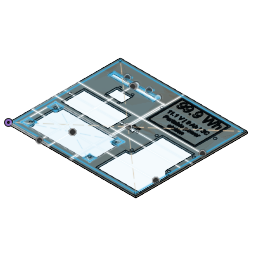
Front panel (Autodesk Fusion 360 design; units mm, degrees)
Autodesk Fusion 360 part; units mm, degrees
sketch "Sketch1" plane through (0, 0, 0) normal (0, 0, 1) x (1, 0, 0)
  line L0 (0, 0) -> (200, 0)
  line L1 (200, 0) -> (200, 150)
  line L2 (200, 150) -> (0, 150)
  line L3 (0, 150) -> (0, 0)
  dimension "d1" = 200
  dimension "d2" = 150
  constraint horizontal L0
  constraint vertical L1
  constraint horizontal L2
  constraint vertical L3
  constraint coincident L0.start L3.end
  measures "d1" distance of L0.start L0.end
  measures "d2" distance of L0.start L2.end
extrude "Extrude1" add sketch "Sketch1" along normal blind 3
sketch "Sketch2" plane through (0, 0, 3) normal (0, 0, 1) x (-1, 0, 0)
  line L0 (0, -150) -> (0, 0)
  line L1 (0, 0) -> (-200, 0)
  line L2 (-200, 0) -> (-200, -150)
  line L3 (-200, -150) -> (0, -150)
  line L4 (-100, -150) -> (-100, 0)
  line L5 (0, -75) -> (-200, -75)
  line L6 (-100, -150) -> (-50, -150)
  line L7 (-50, -150) -> (-50, 0)
  line L8 (0, -75) -> (0, -112.5)
  line L9 (0, -112.5) -> (-200, -112.5)
  line L10 (0, -75) -> (0, -37.5)
  line L11 (0, -37.5) -> (-200, -37.5)
  dimension "d5" = 50
  dimension "d6" = 37.5
  dimension "d7" = 37.5
  constraint midpoint L3 L4.start
  constraint midpoint L1 L4.end
  constraint midpoint L0 L5.start
  constraint midpoint L2 L5.end
  constraint coincident L3 L6.end
  constraint coincident L1 L7.end
  constraint perpendicular L1 L7
  constraint perpendicular L3 L8
  constraint coincident L2 L9.end
  constraint perpendicular L2 L9
  constraint perpendicular L5 L10
  constraint coincident L2 L11.end
  constraint perpendicular L2 L11
  measures "d5" distance of L4.start L6.end
  measures "d6" distance of L5.start L8.end
  measures "d7" distance of L5.start L10.end
sketch "Sketch3" plane through (0, 0, 3) normal (0, 0, 1) x (-1, 0, 0)
  line L0 (-103.25, -144.25) -> (-188.75, -144.25)
  circle A0 centre (-103.25, -144.25) radius 2.1
  circle A1 centre (-188.75, -144.25) radius 2.1
  line L1 (-103.25, -144.25) -> (-146, -144.25)
  line L2 (-194, -126.75) -> (-194, -161.75)
  line L3 (-194, -161.75) -> (-98, -161.75)
  line L4 (-98, -161.75) -> (-98, -126.75)
  line L5 (-98, -126.75) -> (-194, -126.75)
  line L6 (-194, -126.75) -> (-98, -161.75) construction
  line L7 (-194, -161.75) -> (-98, -126.75) construction
  point P0 (-146, -144.25)
  dimension "d8" = 85.5
  dimension "d9" = 4.2
  dimension "d10" = 4.2
  dimension "d11" = 42.75
  dimension "d12" = 35
  dimension "d13" = 96
  constraint coincident L0.start A0.centre
  constraint coincident L0.end A1.centre
  constraint midpoint L0 P0
  constraint perpendicular L2 L3
  constraint parallel L2 L4
  constraint parallel L3 L5
  constraint coincident L6 P0
  constraint coincident L7 P0
  constraint coincident P0 L1.end
  measures "d8" distance of L0.start L0.end
  measures "d9" diameter of A0
  measures "d10" diameter of A1
  measures "d11" distance of L0.start P0
  measures "d12" distance of L3.end L4.end
  measures "d13" distance of L2.end L3.end
sketch "Sketch4" plane through (0, 0, 3) normal (0, 0, 1) x (-1, 0, 0)
  line L0 (-167.8105, -105.7768) -> (-167.8105, -106)
  line L1 (-167.8105, -106) -> (-167.8105, -7.9943)
  line L2 (-202.8105, -7.9972) -> (-132.8105, -7.9972)
  line L3 (-132.8105, -7.9972) -> (-132.8105, -105.9972)
  line L4 (-132.8105, -105.9972) -> (-202.8105, -105.9972)
  line L5 (-202.8105, -105.9972) -> (-202.8105, -7.9972)
  line L6 (-202.8105, -7.9972) -> (-132.8105, -105.9972) construction
  line L7 (-132.8105, -7.9972) -> (-202.8105, -105.9972) construction
  line L8 (-64, -118.5) -> (-38, -118.5)
  line L9 (-38, -118.5) -> (-38, -136.5)
  line L10 (-38, -136.5) -> (-64, -136.5)
  line L11 (-64, -136.5) -> (-64, -118.5)
  line L12 (-64, -118.5) -> (-38, -136.5) construction
  line L13 (-38, -118.5) -> (-64, -136.5) construction
  line L14 (-61.25, -116) -> (-40.75, -116)
  line L15 (-40.75, -116) -> (-40.75, -139)
  line L16 (-40.75, -139) -> (-61.25, -139)
  line L17 (-61.25, -139) -> (-61.25, -116)
  line L18 (-61.25, -116) -> (-40.75, -139) construction
  line L19 (-40.75, -116) -> (-61.25, -139) construction
  circle A0 centre (-40.75, -139) radius 1.7
  circle A1 centre (-61.25, -139) radius 1.7
  circle A2 centre (-40.75, -116) radius 1.7
  circle A3 centre (-61.25, -116) radius 1.7
  point P0 (-167.8105, -56.9972)
  point P1 (-51, -127.5)
  point P2 (-51, -127.5)
  dimension "d15" = 70
  dimension "d16" = 98
  dimension "d17" = 26
  dimension "d18" = 18
  dimension "d19" = 20.5
  dimension "d20" = 23
  dimension "d21" = 3.4
  dimension "d22" = 3.4
  dimension "d23" = 3.4
  dimension "d24" = 3.4
  constraint horizontal L2
  constraint perpendicular L2 L3
  constraint parallel L2 L4
  constraint parallel L3 L5
  constraint coincident L6 P0
  constraint coincident L7 P0
  constraint midpoint L1 P0
  constraint horizontal L8
  constraint perpendicular L8 L9
  constraint parallel L8 L10
  constraint parallel L9 L11
  constraint coincident L12 P2
  constraint coincident L13 P2
  constraint horizontal L14
  constraint perpendicular L14 L15
  constraint parallel L14 L16
  constraint parallel L15 L17
  constraint coincident L18 P2
  constraint coincident L19 P2
  constraint coincident P2 P1
  constraint coincident L15.end L16.start
  constraint coincident L16.end L17.start
  constraint coincident L14.end L15.start
  constraint coincident L14.start L17.end
  measures "d15" distance of L3.end L4.end
  measures "d16" distance of L2.end L3.end
  measures "d17" distance of L9.end L10.end
  measures "d18" distance of L8.end L9.end
  measures "d19" distance of L15.end L16.end
  measures "d20" distance of L14.end L15.end
  measures "d21" diameter of A0
  measures "d22" diameter of A1
  measures "d23" diameter of A2
  measures "d24" diameter of A3
sketch "Sketch5" plane through (0, 0, 3) normal (0, 0, 1) x (-1, 0, 0)
  line L0 (-51, -144) -> (-51, -158)
  line L1 (-51, -158) -> (-68.5, -158)
  line L2 (-68.5, -158) -> (-33.5, -158)
  circle A0 centre (-68.5, -158) radius 1.7
  circle A1 centre (-33.5, -158) radius 1.7
  dimension "d25" = 14
  dimension "d26" = 17.5
  dimension "d27" = 35
  dimension "d28" = 3.4
  dimension "d29" = 3.4
  constraint vertical L0
  constraint perpendicular L0 L1
  constraint parallel L1 L2
  constraint coincident L1.end L2.start
  constraint coincident L2.end A1.centre
  measures "d25" distance of L0.start L0.end
  measures "d26" distance of L0.end L1.end
  measures "d27" distance of L1.end L2.end
  measures "d28" diameter of A0
  measures "d29" diameter of A1
sketch "Sketch6" plane through (0, 0, 3) normal (0, 0, 1) x (-1, 0, 0)
  line L0 (-37, -154.5) -> (-30, -154.5)
  line L1 (-30, -154.5) -> (-30, -161.5)
  line L2 (-30, -161.5) -> (-37, -161.5)
  line L3 (-37, -161.5) -> (-37, -154.5)
  line L4 (-37, -154.5) -> (-30, -161.5) construction
  line L5 (-30, -154.5) -> (-37, -161.5) construction
  line L6 (-72, -154.5) -> (-65, -154.5)
  line L7 (-65, -154.5) -> (-65, -161.5)
  line L8 (-65, -161.5) -> (-72, -161.5)
  line L9 (-72, -161.5) -> (-72, -154.5)
  line L10 (-72, -154.5) -> (-65, -161.5) construction
  line L11 (-65, -154.5) -> (-72, -161.5) construction
  line L12 (-30, -154.5) -> (-16, -154.5)
  line L13 (-72, -154.5) -> (-86, -154.5)
  line L14 (-16, -154.5) -> (-86, -154.5)
  line L15 (-86, -154.5) -> (-86, -147.5)
  line L16 (-86, -147.5) -> (-16, -147.5)
  line L17 (-16, -147.5) -> (-16, -154.5)
  point P0 (-33.5, -158)
  point P1 (-68.5, -158)
  dimension "d30" = 7
  dimension "d31" = 7
  dimension "d32" = 7
  dimension "d33" = 7
  dimension "d34" = 14
  dimension "d35" = 14
  dimension "d36" = 7
  constraint horizontal L0
  constraint perpendicular L0 L1
  constraint parallel L0 L2
  constraint parallel L1 L3
  constraint coincident L4 P0
  constraint coincident L5 P0
  constraint horizontal L6
  constraint perpendicular L6 L7
  constraint parallel L6 L8
  constraint parallel L7 L9
  constraint coincident L10 P1
  constraint coincident L11 P1
  constraint perpendicular L1 L12
  constraint perpendicular L9 L13
  constraint horizontal L14
  constraint vertical L15
  constraint horizontal L16
  constraint vertical L17
  measures "d30" distance of L1.end L2.end
  measures "d31" distance of L0.end L1.end
  measures "d32" distance of L7.end L8.end
  measures "d33" distance of L6.end L7.end
  measures "d34" distance of L0.end L12.end
  measures "d35" distance of L6.start L13.end
  measures "d36" distance of L12.end L16.end
sketch "Sketch7" plane through (0, 0, 3) normal (0, 0, 1) x (-1, 0, 0)
  line L0 (-51, -154.5) -> (-51, -151)
  line L1 (-87, -146.5) -> (-15, -146.5)
  line L2 (-15, -146.5) -> (-15, -155.5)
  line L3 (-15, -155.5) -> (-87, -155.5)
  line L4 (-87, -155.5) -> (-87, -146.5)
  line L5 (-87, -146.5) -> (-15, -155.5) construction
  line L6 (-15, -146.5) -> (-87, -155.5) construction
  point P0 (-51, -151)
  dimension "d37" = 3.5
  dimension "d38" = 72
  dimension "d39" = 9
  constraint vertical L0
  constraint horizontal L1
  constraint perpendicular L1 L2
  constraint parallel L1 L3
  constraint parallel L2 L4
  constraint coincident L5 P0
  constraint coincident L6 P0
  constraint coincident P0 L0.end
  measures "d37" distance of L0.start P0
  measures "d38" distance of L2.end L3.end
  measures "d39" distance of L1.end L2.end
sketch "Sketch8" plane through (0, 0, 3) normal (0, 0, 1) x (-1, 0, 0)
  line L0 (-51, -165) -> (-51, -15)
  line L1 (-13.5, -108.5) -> (-88.5, -108.5)
  line L2 (-88.5, -108.5) -> (-88.5, -71.5)
  line L3 (-88.5, -71.5) -> (-13.5, -71.5)
  line L4 (-13.5, -71.5) -> (-13.5, -108.5)
  line L5 (-13.5, -108.5) -> (-88.5, -71.5) construction
  line L6 (-88.5, -108.5) -> (-13.5, -71.5) construction
  point P0 (-51, -90)
  dimension "d40" = 75
  dimension "d41" = 37
  constraint vertical L0
  constraint horizontal L1
  constraint perpendicular L1 L2
  constraint parallel L1 L3
  constraint parallel L2 L4
  constraint coincident L5 P0
  constraint coincident L6 P0
  constraint midpoint L0 P0
  measures "d40" distance of L2.end L3.end
  measures "d41" distance of L1.end L2.end
extrude "Extrude2" add 1 faces at (200, 50, 1) along direction (1, 0, 0) blind 5
sketch "Sketch9" plane through (0, 0, 3) normal (0, 0, 1) x (-1, 0, 0)
  line L0 (0, 0) -> (-4, 0)
  line L1 (-4, 0) -> (-4, -4)
  line L2 (-4, -4) -> (0, -4)
  line L3 (0, -4) -> (0, 0)
  dimension "d44" = 4
  dimension "d45" = 4
  constraint horizontal L0
  constraint vertical L1
  constraint horizontal L2
  constraint vertical L3
  constraint coincident L0.start L3.end
  measures "d44" distance of L0.start L0.end
  measures "d45" distance of L0.start L2.end
extrude "Extrude3" add 1 faces at (136.6667, 150, 1) along direction (0, 1, 0) blind 30
sketch "Sketch10" plane through (0, 0, 3) normal (0, 0, 1) x (-1, 0, 0)
  line L0 (0, 0) -> (-65, 0)
  line L1 (-65, 0) -> (-65, -38.25)
  line L2 (-120, -10.75) -> (-10, -10.75)
  line L3 (-10, -10.75) -> (-10, -65.75)
  line L4 (-10, -65.75) -> (-120, -65.75)
  line L5 (-120, -65.75) -> (-120, -10.75)
  line L6 (-120, -10.75) -> (-10, -65.75) construction
  line L7 (-10, -10.75) -> (-120, -65.75) construction
  point P0 (-65, -38.25)
  dimension "d50" = 65
  dimension "d51" = 38.25
  dimension "d52" = 110
  dimension "d53" = 55
  constraint coincident L0.start origin
  constraint horizontal L0
  constraint perpendicular L0 L1
  constraint horizontal L2
  constraint perpendicular L2 L3
  constraint parallel L2 L4
  constraint parallel L3 L5
  constraint coincident L6 P0
  constraint coincident L7 P0
  constraint coincident P0 L1.end
  measures "d50" distance of L0.start L0.end
  measures "d51" distance of L0.end P0
  measures "d52" distance of L3.end L4.end
  measures "d53" distance of L2.end L3.end
sketch "Sketch11" plane through (0, 0, 3) normal (0, 0, 1) x (-1, 0, 0)
  line L0 (0, -180) -> (0, 0)
  line L1 (0, 0) -> (-205, 0)
  line L2 (-205, 0) -> (-205, -180)
  line L3 (-205, -180) -> (0, -180)
  line L4 (-88, -146.5) -> (-14, -146.5)
  line L5 (-14, -146.5) -> (-14, -155.5)
  line L6 (-14, -155.5) -> (-88, -155.5)
  line L7 (-88, -155.5) -> (-88, -146.5)
  line L8 (-88, -146.5) -> (-14, -155.5) construction
  line L9 (-14, -146.5) -> (-88, -155.5) construction
  point P0 (-51, -151)
  dimension "d54" = 74
  dimension "d55" = 9
  constraint horizontal L4
  constraint perpendicular L4 L5
  constraint parallel L4 L6
  constraint parallel L5 L7
  constraint coincident L8 P0
  constraint coincident L9 P0
  measures "d54" distance of L5.end L6.end
  measures "d55" distance of L4.end L5.end
sketch "Sketch12" plane through (0, 0, 3) normal (0, 0, 1) x (-1, 0, 0)
  line L0 (-132.75, -106) -> (-141.75, -106)
  line L1 (-141.75, -106) -> (-141.75, -56)
  line L2 (-141.75, -56) -> (-132.75, -56)
  line L3 (-132.75, -56) -> (-132.75, -106)
  line L4 (-202.75, -106) -> (-193.75, -106)
  line L5 (-193.75, -106) -> (-193.75, -56)
  line L6 (-193.75, -56) -> (-202.75, -56)
  line L7 (-202.75, -56) -> (-202.75, -106)
  line L8 (-132.75, -106) -> (-167.75, -106)
  line L9 (-167.75, -106) -> (-167.75, -81)
  line L10 (-197.75, -61) -> (-137.75, -61)
  line L11 (-137.75, -61) -> (-137.75, -101)
  line L12 (-137.75, -101) -> (-197.75, -101)
  line L13 (-197.75, -101) -> (-197.75, -61)
  line L14 (-197.75, -61) -> (-137.75, -101) construction
  line L15 (-137.75, -61) -> (-197.75, -101) construction
  circle A0 centre (-137.75, -61) radius 2.1
  circle A1 centre (-137.75, -101) radius 2.1
  circle A2 centre (-197.75, -101) radius 2.1
  circle A3 centre (-197.75, -61) radius 2.1
  point P0 (-167.75, -81)
  dimension "d56" = 9
  dimension "d57" = 50
  dimension "d58" = 9
  dimension "d59" = 50
  dimension "d60" = 35
  dimension "d61" = 25
  dimension "d62" = 60
  dimension "d63" = 40
  dimension "d64" = 4.2
  dimension "d65" = 4.2
  dimension "d66" = 4.2
  dimension "d67" = 4.2
  constraint horizontal L0
  constraint vertical L1
  constraint horizontal L2
  constraint vertical L3
  constraint horizontal L4
  constraint vertical L5
  constraint horizontal L6
  constraint vertical L7
  constraint perpendicular L7 L8
  constraint perpendicular L8 L9
  constraint horizontal L10
  constraint perpendicular L10 L11
  constraint parallel L10 L12
  constraint parallel L11 L13
  constraint coincident L14 P0
  constraint coincident L15 P0
  constraint coincident P0 L9.end
  constraint coincident L10.end L11.start
  constraint coincident L11.end L12.start
  constraint coincident L12.end L13.start
  constraint coincident L10.start L13.end
  measures "d56" distance of L0.start L0.end
  measures "d57" distance of L0.start L2.end
  measures "d58" distance of L4.start L4.end
  measures "d59" distance of L4.start L6.end
  measures "d60" distance of L0.start L8.end
  measures "d61" distance of L8.end P0
  measures "d62" distance of L11.end L12.end
  measures "d63" distance of L10.end L11.end
  measures "d64" diameter of A0
  measures "d65" diameter of A1
  measures "d66" diameter of A2
  measures "d67" diameter of A3
sketch "Sketch13" plane through (0, 0, 3) normal (0, 0, 1) x (-1, 0, 0)
  line L0 (-112.5, -18.25) -> (-17.5, -18.25)
  line L1 (-17.5, -18.25) -> (-17.5, -58.25)
  line L2 (-17.5, -58.25) -> (-112.5, -58.25)
  line L3 (-112.5, -58.25) -> (-112.5, -18.25)
  line L4 (-112.5, -18.25) -> (-17.5, -58.25) construction
  line L5 (-17.5, -18.25) -> (-112.5, -58.25) construction
  circle A0 centre (-17.5, -58.25) radius 2.1
  circle A1 centre (-112.5, -58.25) radius 2.1
  circle A2 centre (-112.5, -18.25) radius 2.1
  circle A3 centre (-17.5, -18.25) radius 2.1
  line L6 (-9, -90) -> (-93, -90)
  circle A4 centre (-9, -90) radius 2.1
  circle A5 centre (-93, -90) radius 2.1
  point P0 (-65, -38.25)
  point P1 (-51, -90)
  dimension "d68" = 95
  dimension "d69" = 40
  dimension "d70" = 4.2
  dimension "d71" = 4.2
  dimension "d72" = 4.2
  dimension "d73" = 4.2
  dimension "d74" = 84
  dimension "d75" = 4.2
  dimension "d76" = 4.2
  constraint horizontal L0
  constraint perpendicular L0 L1
  constraint parallel L0 L2
  constraint parallel L1 L3
  constraint coincident L4 P0
  constraint coincident L5 P0
  constraint coincident L1.end L2.start
  constraint coincident L2.end L3.start
  constraint coincident L0.start L3.end
  constraint coincident L0.end L1.start
  constraint midpoint L6 P1
  constraint horizontal L6
  constraint coincident L6.start A4.centre
  constraint coincident L6.end A5.centre
  measures "d68" distance of L1.end L2.end
  measures "d69" distance of L0.end L1.end
  measures "d70" diameter of A0
  measures "d71" diameter of A1
  measures "d72" diameter of A2
  measures "d73" diameter of A3
  measures "d74" distance of L6.start L6.end
  measures "d75" diameter of A4
  measures "d76" diameter of A5
sketch "Sketch14" plane through (0, 0, 3) normal (0, 0, 1) x (-1, 0, 0)
  line L0 (-10, -10.75) -> (-22, -10.75)
  line L1 (-22, -10.75) -> (-22, -22.75)
  line L2 (-22, -22.75) -> (-10, -22.75)
  line L3 (-10, -22.75) -> (-10, -10.75)
  line L4 (-10, -65.75) -> (-22, -65.75)
  line L5 (-22, -65.75) -> (-22, -53.75)
  line L6 (-22, -53.75) -> (-10, -53.75)
  line L7 (-10, -53.75) -> (-10, -65.75)
  line L8 (-120, -65.75) -> (-110, -65.75)
  line L9 (-110, -65.75) -> (-110, -55.75)
  line L10 (-110, -55.75) -> (-120, -55.75)
  line L11 (-120, -55.75) -> (-120, -65.75)
  line L12 (-120, -10.75) -> (-110, -10.75)
  line L13 (-110, -10.75) -> (-110, -20.75)
  line L14 (-110, -20.75) -> (-120, -20.75)
  line L15 (-120, -20.75) -> (-120, -10.75)
  dimension "d77" = 12
  dimension "d78" = 12
  dimension "d79" = 12
  dimension "d80" = 12
  dimension "d81" = 10
  dimension "d82" = 10
  dimension "d83" = 10
  constraint horizontal L0
  constraint vertical L1
  constraint horizontal L2
  constraint vertical L3
  constraint horizontal L4
  constraint vertical L5
  constraint horizontal L6
  constraint vertical L7
  constraint horizontal L8
  constraint vertical L9
  constraint horizontal L10
  constraint vertical L11
  constraint horizontal L12
  constraint vertical L13
  constraint horizontal L14
  constraint vertical L15
  measures "d77" distance of L0.start L0.end
  measures "d78" distance of L0.start L2.end
  measures "d79" distance of L4.start L4.end
  measures "d80" distance of L4.start L6.end
  measures "d81" distance of L8.start L10.end
  measures "d82" distance of L12.start L12.end
  measures "d83" distance of L12.start L14.end
sketch "Sketch15" plane through (0, 0, 3) normal (0, 0, 1) x (-1, 0, 0)
  line L0 (0, -180) -> (-102.5, -180)
  line L1 (-102.5, -180) -> (-102.5, 0)
  line L2 (-113.5, -86.5) -> (-106.5, -86.5)
  line L3 (-106.5, -86.5) -> (-106.5, -93.5)
  line L4 (-106.5, -93.5) -> (-113.5, -93.5)
  line L5 (-113.5, -93.5) -> (-113.5, -86.5)
  line L6 (-113.5, -86.5) -> (-106.5, -93.5) construction
  line L7 (-106.5, -86.5) -> (-113.5, -93.5) construction
  line L8 (-102.5, -90) -> (-117.5, -90)
  circle A0 centre (-102.5, -90) radius 1.7
  circle A1 centre (-117.5, -90) radius 1.7
  point P0 (-110, -90)
  point P1 (-110, -90)
  dimension "d84" = 102.5
  dimension "d85" = 7
  dimension "d86" = 7
  dimension "d87" = 15
  dimension "d88" = 3.4
  dimension "d89" = 3.4
  constraint horizontal L0
  constraint perpendicular L0 L1
  constraint horizontal L2
  constraint perpendicular L2 L3
  constraint parallel L2 L4
  constraint parallel L3 L5
  constraint coincident L6 P1
  constraint coincident L7 P1
  constraint midpoint L8 P1
  constraint coincident P1 P0
  constraint perpendicular L5 L8
  constraint coincident L8.start A0.centre
  constraint coincident L8.end A1.centre
  measures "d84" distance of L0.start L0.end
  measures "d85" distance of L3.end L4.end
  measures "d86" distance of L2.end L3.end
  measures "d87" distance of L8.start L8.end
  measures "d88" diameter of A0
  measures "d89" diameter of A1
sketch "Sketch16" plane through (0, 0, 3) normal (0, 0, 1) x (-1, 0, 0)
  line L0 (-17.5, -53.75) -> (-17.5, -22.75)
  line L1 (-17.5, -22.75) -> (-22, -22.75)
  line L2 (-22, -22.75) -> (-22, -10.75)
  line L3 (-22, -10.75) -> (-110, -10.75)
  line L4 (-110, -10.75) -> (-110, -20.75)
  line L5 (-110, -20.75) -> (-120, -20.75)
  line L6 (-120, -20.75) -> (-120, -55.75)
  line L7 (-120, -55.75) -> (-110, -55.75)
  line L8 (-110, -55.75) -> (-110, -65.75)
  line L9 (-110, -65.75) -> (-22, -65.75)
  line L10 (-22, -65.75) -> (-22, -53.75)
  line L11 (-22, -53.75) -> (-17.5, -53.75)
  line L12 (-141.75, -106) -> (-141.75, -56)
  line L13 (-141.75, -56) -> (-132.75, -56)
  line L14 (-132.75, -56) -> (-132.75, -8)
  line L15 (-132.75, -8) -> (-202.8, -8)
  line L16 (-132.75, -8) -> (-202.8, -8)
  line L17 (-202.8, -8) -> (-202.8, -56)
  line L18 (-202.8, -56) -> (-193.8, -56)
  line L19 (-193.8, -56) -> (-193.8, -106)
  line L20 (-193.8, -106) -> (-141.75, -106)
  dimension "d90" = 90
  dimension "d91" = 48
  dimension "d92" = 70.05
  constraint vertical L0
  constraint perpendicular L0 L1
  constraint perpendicular L1 L2
  constraint perpendicular L0 L3
  constraint perpendicular L3 L4
  constraint perpendicular L4 L5
  constraint perpendicular L5 L6
  constraint perpendicular L6 L7
  constraint perpendicular L7 L8
  constraint perpendicular L8 L9
  constraint perpendicular L9 L10
  constraint perpendicular L0 L11
  constraint perpendicular L9 L12
  constraint perpendicular L8 L13
  constraint perpendicular L14 L15
  constraint perpendicular L15 L17
  constraint perpendicular L17 L18
  constraint perpendicular L15 L19
  measures "d90" angle of L13 L14
  measures "d91" distance of L13.end L14.end
  measures "d92" distance of L14.end L15.end
extrude "Extrude4" cut sketch "Sketch16" sketch "Sketch13" sketch "Sketch8" sketch "Sketch4" sketch "Sketch11" sketch "Sketch5" sketch "Sketch3" sketch "Sketch15" sketch "Sketch12" against normal blind 8767865 of sketch 2 contours L0 L3 A2 | L0 L3 A2 | L0 L1 A3 | L0 L1 A3 | L2 L3 A1 | L2 L3 A1 | L1 L2 A0 | L1 L2 A0 | A4 | A5 of sketch 3 of sketch 4 contours L8 L10 L11 L17 | L8 L10 L15 L17 | L8 L9 L10 L15 | L14 L17 A3 | L14 L17 A3 | L14 L15 A2 | L14 L15 A2 | L16 L17 A1 | L16 L17 A1 | L15 L16 A0 | L15 L16 A0 of sketch 5 contours L4 L5 L6 L7 of sketch 6 of sketch 7 contours A0 | A1 of sketch 8 of sketch 9 contours L11 L12 A1 | L11 L12 A1 | L10 L11 A0 | L10 L11 A0 | L10 L13 A3 | L10 L13 A3 | L12 L13 A2 | L12 L13 A2
sketch "Sketch17" plane through (0, 0, 3) normal (0, 0, 1) x (-1, 0, 0)
  line L0 (0, -180) -> (0, 0)
  line L1 (0, 0) -> (-205, 0)
  line L2 (-205, 0) -> (-205, -180)
  line L3 (-205, -180) -> (0, -180)
  circle A0 centre (-197.75, -101) radius 2.1
  circle A1 centre (-137.75, -101) radius 2.1
  circle A2 centre (-117.5, -90) radius 1.7
  circle A3 centre (-102.5, -90) radius 1.7
  circle A4 centre (-103.25, -144.25) radius 2.1
  circle A5 centre (-33.5, -158) radius 1.7
  circle A6 centre (-40.75, -116) radius 1.7
  line L4 (-38, -118.5) -> (-38, -136.5)
  line L5 (-38, -136.5) -> (-64, -136.5)
  line L6 (-64, -136.5) -> (-64, -118.5)
  line L7 (-64, -118.5) -> (-38, -118.5)
  circle A7 centre (-61.25, -116) radius 1.7
  circle A8 centre (-112.5, -18.25) radius 2.1
  circle A9 centre (-93, -90) radius 2.1
  circle A10 centre (-9, -90) radius 2.1
  line L8 (-17.5, -22.75) -> (-17.5, -53.75)
  line L9 (-17.5, -53.75) -> (-22, -53.75)
  line L10 (-22, -53.75) -> (-22, -65.75)
  line L11 (-22, -65.75) -> (-110, -65.75)
  line L12 (-110, -65.75) -> (-110, -55.75)
  line L13 (-110, -55.75) -> (-120, -55.75)
  line L14 (-120, -55.75) -> (-120, -20.75)
  line L15 (-120, -20.75) -> (-110, -20.75)
  line L16 (-110, -20.75) -> (-110, -10.75)
  line L17 (-110, -10.75) -> (-22, -10.75)
  line L18 (-22, -10.75) -> (-22, -22.75)
  line L19 (-22, -22.75) -> (-17.5, -22.75)
  line L20 (-141.75, -56) -> (-141.75, -106)
  line L21 (-141.75, -106) -> (-193.8, -106)
  line L22 (-193.8, -106) -> (-193.8, -56)
  line L23 (-193.8, -56) -> (-202.8, -56)
  line L24 (-202.8, -56) -> (-202.8, -8)
  line L25 (-202.8, -8) -> (-132.75, -8)
  line L26 (-132.75, -8) -> (-132.75, -56)
  line L27 (-132.75, -56) -> (-141.75, -56)
  circle A11 centre (-112.5, -58.25) radius 2.1
  circle A12 centre (-17.5, -58.25) radius 2.1
  circle A13 centre (-17.5, -18.25) radius 2.1
  line L28 (-88.5, -108.5) -> (-88.5, -71.5)
  line L29 (-88.5, -71.5) -> (-13.5, -71.5)
  line L30 (-13.5, -71.5) -> (-13.5, -108.5)
  line L31 (-13.5, -108.5) -> (-88.5, -108.5)
  circle A14 centre (-40.75, -139) radius 1.7
  circle A15 centre (-61.25, -139) radius 1.7
  line L32 (-14, -146.5) -> (-14, -155.5)
  line L33 (-14, -155.5) -> (-88, -155.5)
  line L34 (-88, -155.5) -> (-88, -146.5)
  line L35 (-88, -146.5) -> (-14, -146.5)
  circle A16 centre (-68.5, -158) radius 1.7
  circle A17 centre (-188.75, -144.25) radius 2.1
  line L36 (-106.5, -86.5) -> (-106.5, -93.5)
  line L37 (-106.5, -93.5) -> (-113.5, -93.5)
  line L38 (-113.5, -93.5) -> (-113.5, -86.5)
  line L39 (-113.5, -86.5) -> (-106.5, -86.5)
  circle A18 centre (-197.75, -61) radius 2.1
  circle A19 centre (-137.75, -61) radius 2.1
  line L40 (-110, -170) -> (-180, -170)
  line L41 (-180, -170) -> (-180, -120)
  line L42 (-180, -120) -> (-110, -120)
  line L43 (-110, -120) -> (-110, -170)
  line L44 (-110, -140) -> (-180, -140) construction
  line L45 (-180, -140) -> (-180, -170) construction
  line L46 (-180, -170) -> (-110, -170) construction
  line L47 (-110, -170) -> (-110, -140) construction
  line L48 (-110, -140) -> (-180, -140) construction
  line L49 (-180, -140) -> (-180, -150) construction
  line L50 (-180, -150) -> (-110, -150) construction
  line L51 (-110, -150) -> (-110, -140) construction
  line L52 (-110, -120) -> (-180, -120) construction
  line L53 (-180, -120) -> (-180, -140) construction
  line L54 (-180, -140) -> (-110, -140) construction
  line L55 (-110, -140) -> (-110, -120) construction
  dimension "d95" = 13
  dimension "d96" = 0
  dimension "d97" = 6
  dimension "d98" = 0
  dimension "d99" = 6
  text T0 "99.9 Wh" font "Arial" height 13 align centre top in box 70 x 30 at (-110, -140) x (-1, 0) y (0, -1) spacing 1 kerned
  text T1 "11.1 V | 9 Ah | 3C" font "Arial" height 6 align centre middle in box 70 x 10 at (-110, -140) x (-1, 0) y (0, -1) spacing 1 kerned
  text T2 "Portable power station" font "Arial" height 6 align centre middle in box 70 x 20 at (-110, -120) x (-1, 0) y (0, -1) spacing 1 kerned
  constraint horizontal L40
  constraint vertical L41
  constraint horizontal L42
  constraint vertical L43
  constraint coincident L41
  constraint coincident L40.start
  constraint coincident L43
  constraint coincident L47
  constraint coincident L41.end
sketch "Sketch18" plane through (0, 0, 3) normal (0, 0, 1) x (-1, 0, 0)
  line L0 (-110, -170) -> (-110, -145)
  line L1 (-110, -145) -> (-145, -145)
  line L2 (-108, -118) -> (-182, -118)
  line L3 (-182, -118) -> (-182, -172)
  line L4 (-182, -172) -> (-108, -172)
  line L5 (-108, -172) -> (-108, -118)
  line L6 (-108, -118) -> (-182, -172) construction
  line L7 (-182, -118) -> (-108, -172) construction
  line L8 (-184, -116) -> (-106, -116)
  line L9 (-106, -116) -> (-106, -174)
  line L10 (-106, -174) -> (-184, -174)
  line L11 (-184, -174) -> (-184, -116)
  line L12 (-184, -116) -> (-106, -174) construction
  line L13 (-106, -116) -> (-184, -174) construction
  point P0 (-145, -145)
  point P1 (-145, -145)
  dimension "d101" = 25
  dimension "d102" = 35
  dimension "d103" = 74
  dimension "d104" = 54
  dimension "d105" = 78
  dimension "d106" = 58
  constraint vertical L0
  constraint perpendicular L0 L1
  constraint horizontal L2
  constraint perpendicular L2 L3
  constraint parallel L2 L4
  constraint parallel L3 L5
  constraint coincident L6 P1
  constraint coincident L7 P1
  constraint coincident P1 P0
  constraint horizontal L8
  constraint perpendicular L8 L9
  constraint parallel L8 L10
  constraint parallel L9 L11
  constraint coincident L12 P1
  constraint coincident L13 P1
  measures "d101" distance of L0.start L0.end
  measures "d102" distance of L0.end P1
  measures "d103" distance of L3.end L4.end
  measures "d104" distance of L2.end L3.end
  measures "d105" distance of L9.end L10.end
  measures "d106" distance of L8.end L9.end
extrude "Extrude5" cut sketch "Sketch18" sketch "Sketch17" against normal blind 0.5 of sketch 2 text T0 T1 T2
sketch "Sketch19" plane through (0, 0, 3) normal (0, 0, 1) x (-1, 0, 0)
  circle A0 centre (-137.75, -61) radius 2.1
  circle A1 centre (-197.75, -61) radius 2.1
  line L0 (-106.5, -86.5) -> (-106.5, -93.5)
  line L1 (-106.5, -93.5) -> (-113.5, -93.5)
  line L2 (-113.5, -93.5) -> (-113.5, -86.5)
  line L3 (-113.5, -86.5) -> (-106.5, -86.5)
  circle A2 centre (-188.75, -144.25) radius 2.1
  circle A3 centre (-68.5, -158) radius 1.7
  line L4 (-14, -146.5) -> (-14, -155.5)
  line L5 (-14, -155.5) -> (-88, -155.5)
  line L6 (-88, -155.5) -> (-88, -146.5)
  line L7 (-88, -146.5) -> (-14, -146.5)
  circle A4 centre (-61.25, -139) radius 1.7
  circle A5 centre (-40.75, -139) radius 1.7
  line L8 (-88.5, -108.5) -> (-88.5, -71.5)
  line L9 (-88.5, -71.5) -> (-13.5, -71.5)
  line L10 (-13.5, -71.5) -> (-13.5, -108.5)
  line L11 (-13.5, -108.5) -> (-88.5, -108.5)
  circle A6 centre (-17.5, -18.25) radius 2.1
  circle A7 centre (-17.5, -58.25) radius 2.1
  circle A8 centre (-112.5, -58.25) radius 2.1
  line L12 (-141.75, -56) -> (-141.75, -106)
  line L13 (-141.75, -106) -> (-193.8, -106)
  line L14 (-193.8, -106) -> (-193.8, -56)
  line L15 (-193.8, -56) -> (-202.8, -56)
  line L16 (-202.8, -56) -> (-202.8, -8)
  line L17 (-202.8, -8) -> (-132.75, -8)
  line L18 (-132.75, -8) -> (-132.75, -56)
  line L19 (-132.75, -56) -> (-141.75, -56)
  line L20 (-17.5, -22.75) -> (-17.5, -53.75)
  line L21 (-17.5, -53.75) -> (-22, -53.75)
  line L22 (-22, -53.75) -> (-22, -65.75)
  line L23 (-22, -65.75) -> (-110, -65.75)
  line L24 (-110, -65.75) -> (-110, -55.75)
  line L25 (-110, -55.75) -> (-120, -55.75)
  line L26 (-120, -55.75) -> (-120, -20.75)
  line L27 (-120, -20.75) -> (-110, -20.75)
  line L28 (-110, -20.75) -> (-110, -10.75)
  line L29 (-110, -10.75) -> (-22, -10.75)
  line L30 (-22, -10.75) -> (-22, -22.75)
  line L31 (-22, -22.75) -> (-17.5, -22.75)
  circle A9 centre (-9, -90) radius 2.1
  circle A10 centre (-93, -90) radius 2.1
  circle A11 centre (-112.5, -18.25) radius 2.1
  circle A12 centre (-61.25, -116) radius 1.7
  line L32 (-38, -118.5) -> (-38, -136.5)
  line L33 (-38, -136.5) -> (-64, -136.5)
  line L34 (-64, -136.5) -> (-64, -118.5)
  line L35 (-64, -118.5) -> (-38, -118.5)
  circle A13 centre (-40.75, -116) radius 1.7
  circle A14 centre (-33.5, -158) radius 1.7
  circle A15 centre (-103.25, -144.25) radius 2.1
  circle A16 centre (-102.5, -90) radius 1.7
  circle A17 centre (-117.5, -90) radius 1.7
  circle A18 centre (-137.75, -101) radius 2.1
  circle A19 centre (-197.75, -101) radius 2.1
  line L36 (0, -180) -> (0, 0)
  line L37 (0, 0) -> (-205, 0)
  line L38 (-205, 0) -> (-205, -180)
  line L39 (-205, -180) -> (0, -180)
  line L40 (-106, -116) -> (-106, -174)
  line L41 (-106, -174) -> (-184, -174)
  line L42 (-184, -174) -> (-184, -116)
  line L43 (-184, -116) -> (-106, -116)
  line L44 (-102.5, -180) -> (-102.5, 0)
  line L45 (0, -90) -> (-205, -90)
  constraint midpoint L39 L44.start
  constraint midpoint L37 L44.end
  constraint midpoint L36 L45.start
  constraint midpoint L38 L45.end
sketch "Sketch20" plane through (0, 0, 3) normal (0, 0, 1) x (-1, 0, 0)
  line L0 (-4, -4) -> (-201, -4)
  line L1 (-201, -4) -> (-201, -176)
  line L2 (-201, -176) -> (-4, -176)
  line L3 (-4, -176) -> (-4, -4)
  line L4 (-4, -4) -> (-201, -176) construction
  line L5 (-201, -4) -> (-4, -176) construction
  point P0 (-102.5, -90)
  dimension "d109" = 197
  dimension "d110" = 172
  constraint horizontal L0
  constraint perpendicular L0 L1
  constraint parallel L0 L2
  constraint parallel L1 L3
  constraint coincident L4 P0
  constraint coincident L5 P0
  measures "d109" distance of L1.end L2.end
  measures "d110" distance of L0.end L1.end
sketch "Sketch21" plane through (0, 0, 3) normal (0, 0, 1) x (-1, 0, 0)
  circle A0 centre (-201, -4) radius 2.1
  circle A1 centre (-4, -4) radius 2.1
  circle A2 centre (-4, -176) radius 2.1
  circle A3 centre (-201, -176) radius 2.1
  dimension "d111" = 4.2
  dimension "d112" = 4.2
  dimension "d113" = 4.2
  dimension "d114" = 4.2
  measures "d111" diameter of A0
  measures "d112" diameter of A1
  measures "d113" diameter of A2
  measures "d114" diameter of A3
extrude "Extrude6" cut sketch "Sketch21" against normal blind 46456
sketch "Sketch22" plane through (0, 0, 3) normal (0, 0, 1) x (-1, 0, 0)
  line L0 (-102, -94) -> (-118, -94) construction
  line L1 (-118, -94) -> (-118, -100) construction
  line L2 (-118, -100) -> (-102, -100) construction
  line L3 (-102, -100) -> (-102, -94) construction
  dimension "d117" = 3
  text T0 "Power" font "Arial" height 3 align centre middle in box 16 x 6 at (-102, -94) x (-1, 0) y (0, -1) spacing 1 kerned
extrude "Extrude7" cut sketch "Sketch22" against normal blind 0.5 text T0
fillet "Fillet1" radius 5 2 edges at (22, 53.75, 1.5) (22, 22.75, 1.5)
fillet "Fillet2" radius 1 2 edges at (110, 55.75, 1.5) (110, 20.75, 1.5)
fillet "Fillet3" radius 5 2 edges at (141.75, 56, 1.5) (193.8, 56, 1.5)
sketch "Sketch23" plane through (0, 0, 3) normal (0, 0, 1) x (-1, 0, 0)
  circle A0 centre (-4, -4) radius 2.1
  circle A1 centre (-4, -4) radius 1.7
  circle A2 centre (-201, -4) radius 2.1
  circle A3 centre (-201, -4) radius 1.7
  circle A4 centre (-201, -176) radius 2.1
  circle A5 centre (-201, -176) radius 1.7
  circle A6 centre (-4, -176) radius 2.1
  circle A7 centre (-4, -176) radius 1.7
  dimension "d127" = 4.2
  dimension "d128" = 3.4
  dimension "d129" = 4.2
  dimension "d130" = 3.4
  dimension "d132" = 4.2
  dimension "d133" = 3.4
  dimension "d134" = 4.2
  dimension "d135" = 3.4
  constraint concentric A0 A1
  constraint concentric A2 A3
  constraint concentric A4 A5
  constraint concentric A6 A7
  measures "d127" diameter of A0
  measures "d128" diameter of A1
  measures "d129" diameter of A2
  measures "d130" diameter of A3
  measures "d132" diameter of A4
  measures "d133" diameter of A5
  measures "d134" diameter of A6
  measures "d135" diameter of A7
extrude "Extrude8" add sketch "Sketch23" against normal blind 3
equation "d6 = ( 75 / 2 ) * 1 mm"
equation "d11 = ( 85.500 / 2 ) * 1 mm"
equation "d26 = ( 35 / 2 ) * 1 mm"
equation "d37 = ( 7 / 2 ) * 1 mm"
equation "d50 = ( 130 / 2 ) * 1 mm"
equation "d51 = ( 76.5 / 2 ) * 1 mm"
equation "d84 = ( 205 / 2 ) * 1 mm"
equation "d96 = '99.9 Wh'"
equation "d98 = '11.1 V | 9 Ah | 3C'"
equation "d100 = 'Portable power station'"
equation "d118 = 'Power'"
